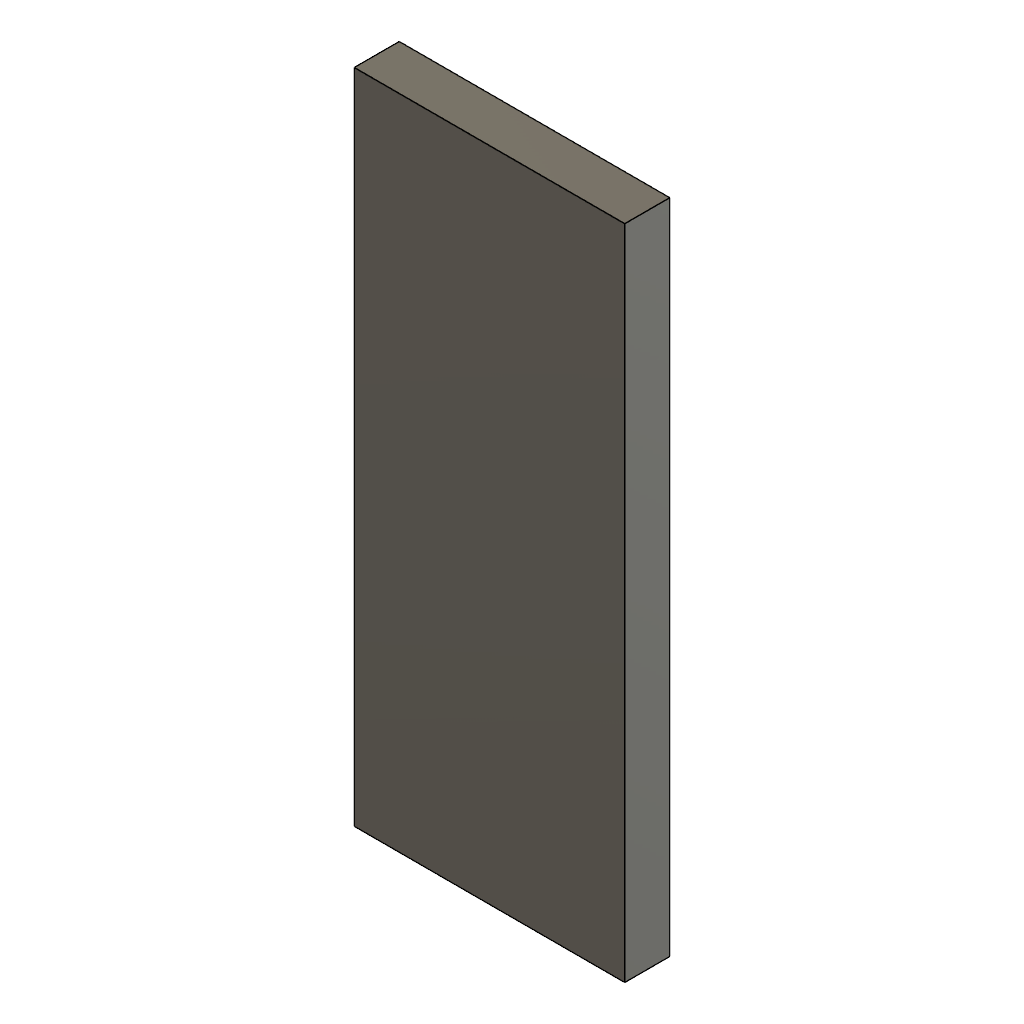
Switchn't (Autodesk Fusion 360 archive; units mm, degrees)
design "Pico"
part number: 2026-10-30-01-21-40-497
Autodesk Fusion 360 part; units mm, degrees
sketch "Sketch1" plane through (0, 0, 0) normal (0, 0, 1) x (1, 0, 0)
  line L0 (-10.5, -25.5) -> (10.5, -25.5)
  line L1 (10.5, -25.5) -> (10.5, 25.5)
  line L2 (10.5, 25.5) -> (-10.5, 25.5)
  line L3 (-10.5, 25.5) -> (-10.5, -25.5)
  line L4 (-10.5, -25.5) -> (10.5, 25.5) construction
  line L5 (10.5, -25.5) -> (-10.5, 25.5) construction
  dimension "d1" = 21
  dimension "d2" = 51
  constraint horizontal L0
  constraint perpendicular L0 L1
  constraint parallel L0 L2
  constraint parallel L1 L3
  constraint coincident L4 origin
  constraint coincident L5 origin
  measures "d1" distance of L1.end L2.end
  measures "d2" distance of L0.end L1.end
extrude "Extrude1" add sketch "Sketch1" along normal blind 3.5

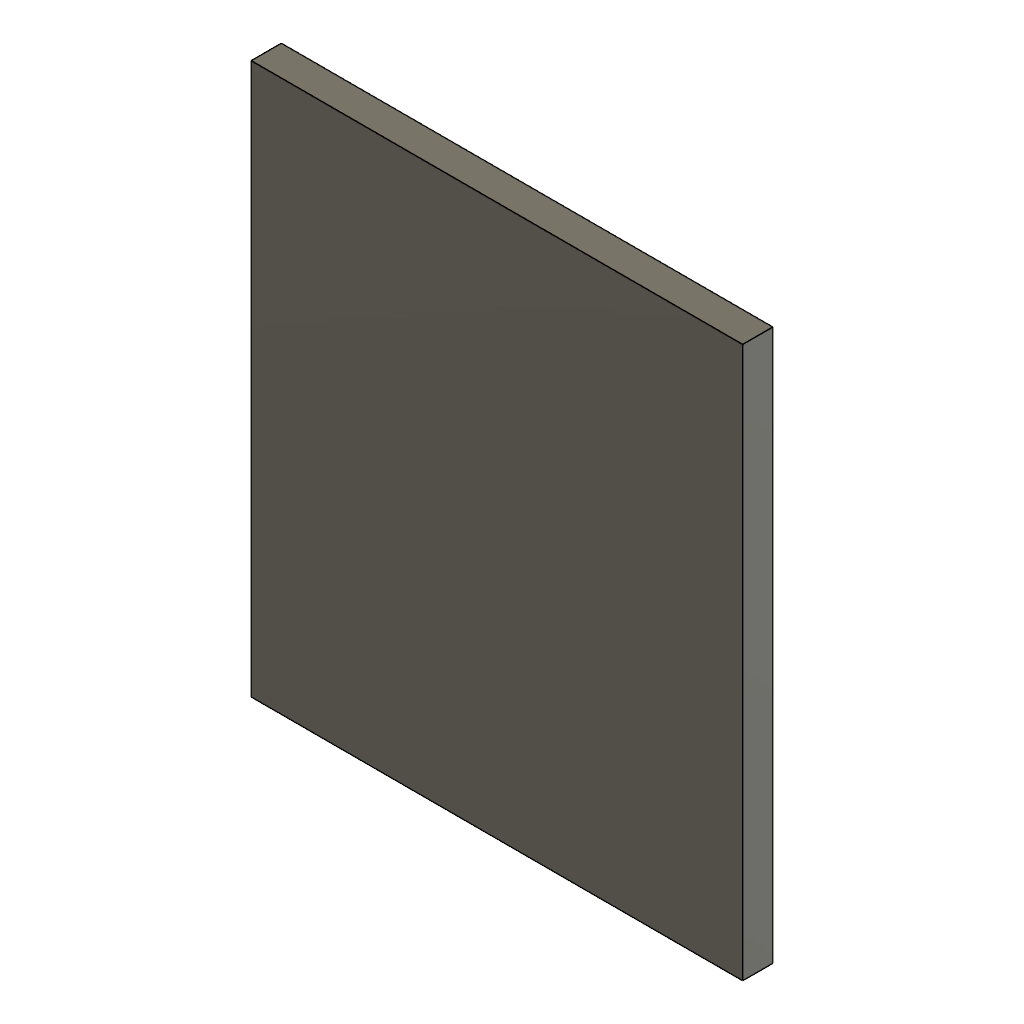
design "display"
part number: 2026-10-30-01-13-21-698
Autodesk Fusion 360 part; units mm, degrees
sketch "Sketch1" plane through (0, 0, 0) normal (0, 0, 1) x (1, 0, 0)
  line L0 (13, 14.575) -> (-13, 14.575)
  line L1 (-13, 14.575) -> (-13, -14.575)
  line L2 (-13, -14.575) -> (13, -14.575)
  line L3 (13, -14.575) -> (13, 14.575)
  line L4 (13, 14.575) -> (-13, -14.575) construction
  line L5 (-13, 14.575) -> (13, -14.575) construction
  dimension "d1" = 26
  dimension "d2" = 29.15
  constraint horizontal L0
  constraint perpendicular L0 L1
  constraint parallel L0 L2
  constraint parallel L1 L3
  constraint coincident L4 origin
  constraint coincident L5 origin
  measures "d1" distance of L1.end L2.end
  measures "d2" distance of L0.end L1.end
extrude "Extrude1" add sketch "Sketch1" along normal blind 1.6

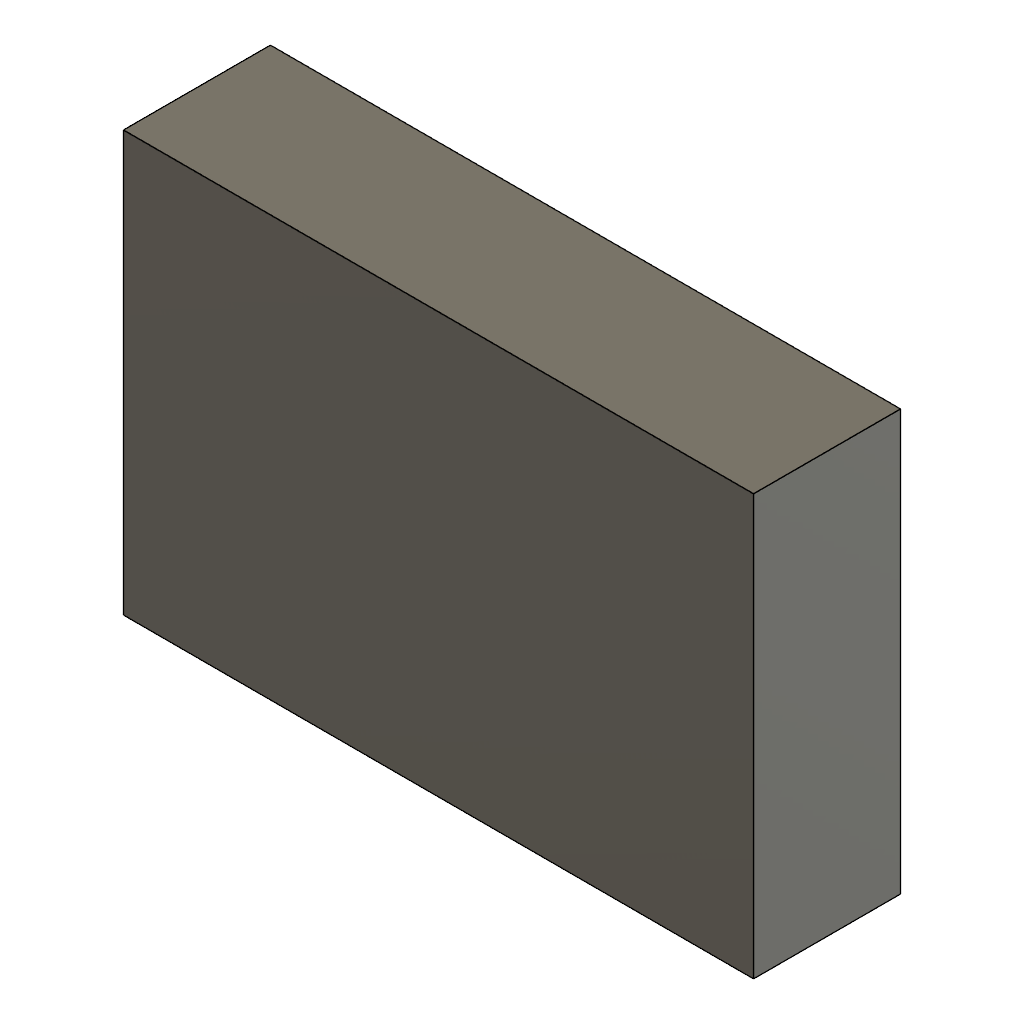
design "Speaker"
part number: 2026-10-30-01-26-45-037
Autodesk Fusion 360 part; units mm, degrees
sketch "Sketch1" plane through (0, 0, 0) normal (0, 0, 1) x (1, 0, 0)
  line L0 (-15, -10) -> (15, -10)
  line L1 (15, -10) -> (15, 10)
  line L2 (15, 10) -> (-15, 10)
  line L3 (-15, 10) -> (-15, -10)
  line L4 (-15, -10) -> (15, 10) construction
  line L5 (15, -10) -> (-15, 10) construction
  dimension "d1" = 30
  dimension "d2" = 20
  constraint horizontal L0
  constraint perpendicular L0 L1
  constraint parallel L0 L2
  constraint parallel L1 L3
  constraint coincident L4 origin
  constraint coincident L5 origin
  measures "d1" distance of L1.end L2.end
  measures "d2" distance of L0.end L1.end
extrude "Extrude1" add sketch "Sketch1" along normal blind 7

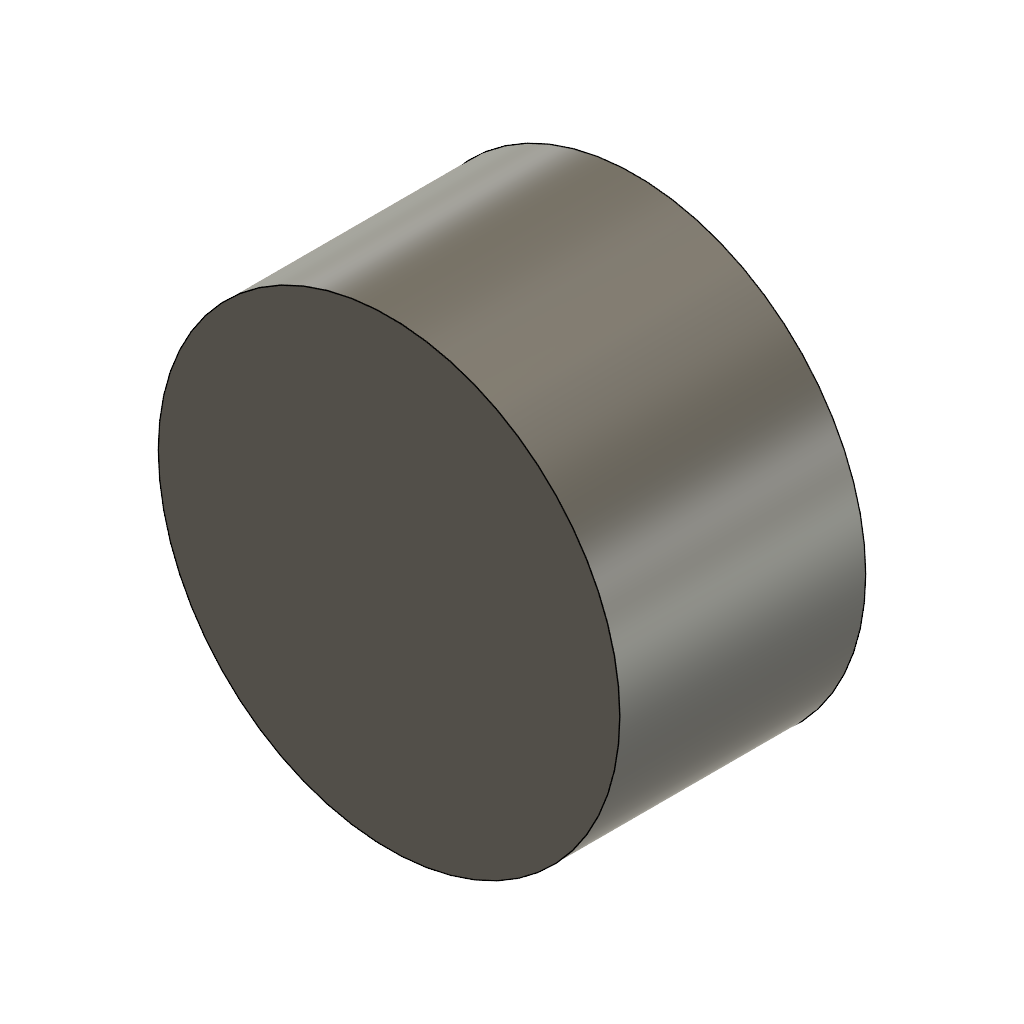
design "Buzzer"
part number: 2026-10-30-01-23-30-754
Autodesk Fusion 360 part; units mm, degrees
sketch "Sketch1" plane through (0, 0, 0) normal (0, 0, 1) x (1, 0, 0)
  circle A0 centre (0, 0) radius 6.1
  dimension "d1" = 12.2
  constraint coincident A0.centre origin
  measures "d1" diameter of A0
extrude "Extrude1" add sketch "Sketch1" along normal blind 6.5

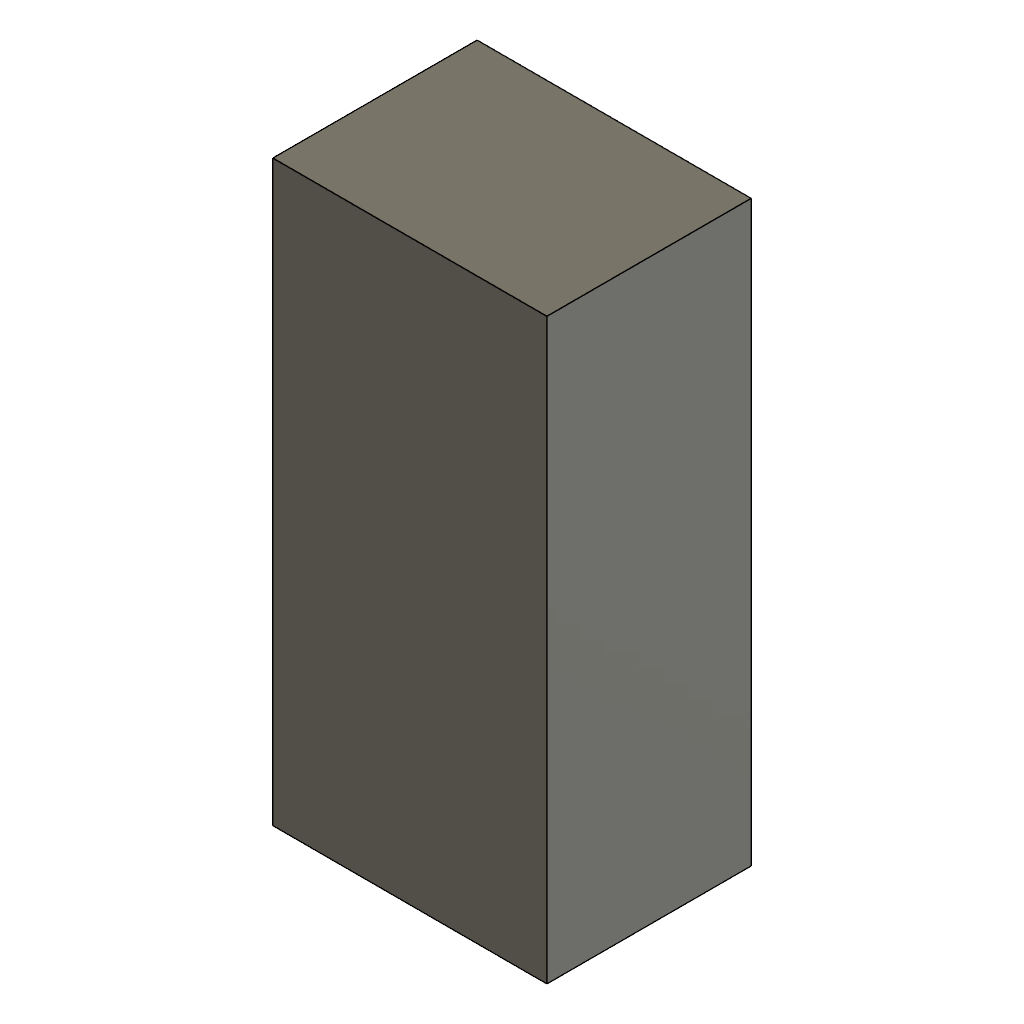
design "Slidey switch"
part number: 2026-10-30-01-30-20-062
Autodesk Fusion 360 part; units mm, degrees
sketch "Sketch1" plane through (0, 0, 0) normal (0, 0, 1) x (1, 0, 0)
  line L0 (-0.3946, -5.8) -> (5.1054, -5.8)
  line L1 (5.1054, -5.8) -> (5.1054, 5.8)
  line L2 (5.1054, 5.8) -> (-0.3946, 5.8)
  line L3 (-0.3946, 5.8) -> (-0.3946, -5.8)
  line L4 (-0.3946, -5.8) -> (5.1054, 5.8) construction
  line L5 (5.1054, -5.8) -> (-0.3946, 5.8) construction
  point P0 (2.3554, 0)
  dimension "d1" = 5.5
  dimension "d2" = 11.6
  constraint horizontal L0
  constraint perpendicular L0 L1
  constraint parallel L0 L2
  constraint parallel L1 L3
  constraint coincident L4 P0
  constraint coincident L5 P0
  measures "d1" distance of L1.end L2.end
  measures "d2" distance of L0.end L1.end
extrude "Extrude1" add sketch "Sketch1" along normal blind 4.1

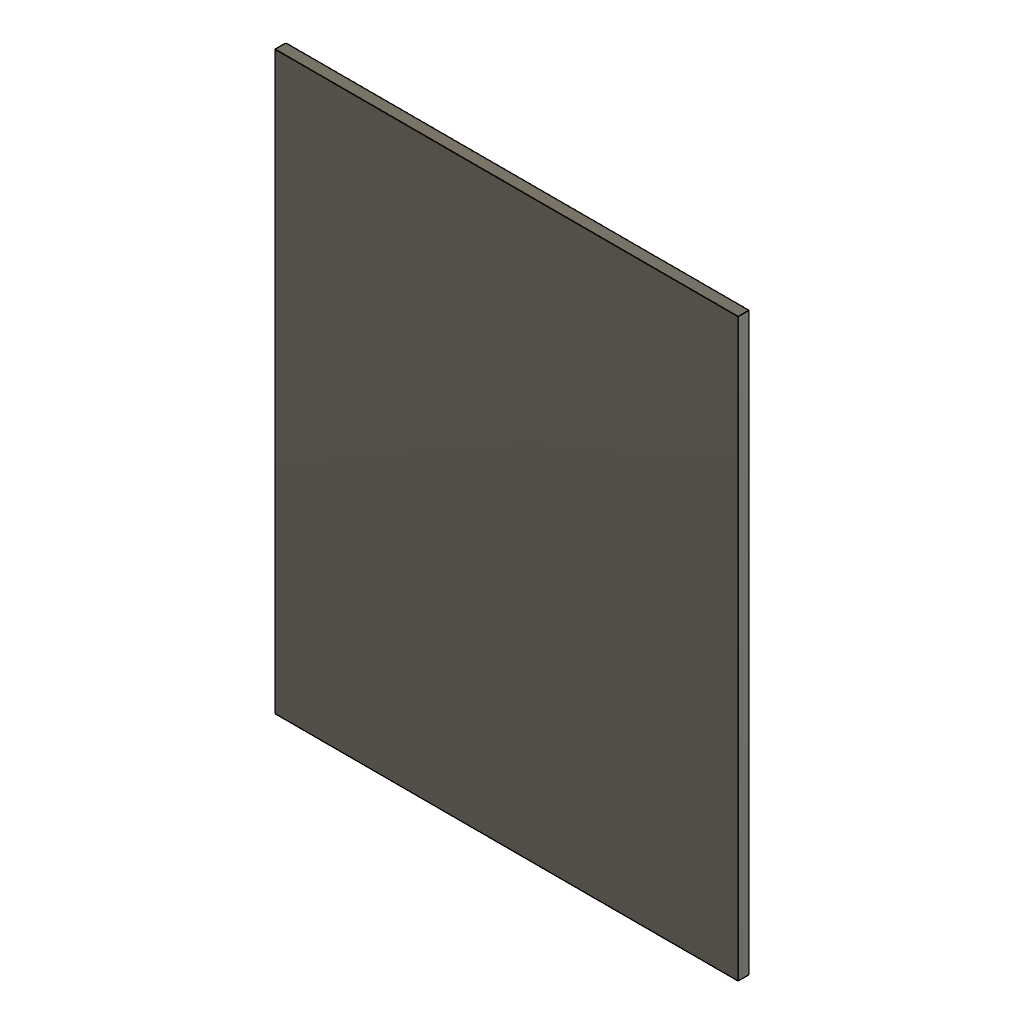
design "PCB"
part number: 2026-10-30-01-00-50-641
Autodesk Fusion 360 part; units mm, degrees
sketch "Sketch1" plane through (0, 0, 0) normal (0, 0, 1) x (1, 0, 0)
  line L0 (34, 42.25) -> (-34, 42.25)
  line L1 (-34, 42.25) -> (-34, -42.25)
  line L2 (-34, -42.25) -> (34, -42.25)
  line L3 (34, -42.25) -> (34, 42.25)
  line L4 (34, 42.25) -> (-34, -42.25) construction
  line L5 (-34, 42.25) -> (34, -42.25) construction
  dimension "d10" = 68
  dimension "d11" = 84.5
  constraint horizontal L0
  constraint perpendicular L0 L1
  constraint parallel L0 L2
  constraint parallel L1 L3
  constraint coincident L4 origin
  constraint coincident L5 origin
  measures "d10" distance of L1.end L2.end
  measures "d11" distance of L0.end L1.end
extrude "Extrude1" add sketch "Sketch1" along normal blind 1.6
equation "PCBwidth = 68 mm"
equation "PCBlength = 84.5 mm"
equation "PCBheight = 1.6 mm"
equation "Clearence = 0.3 mm"
equation "Wallthickness = 2 mm"
equation "insidewidth = 70 mm"
equation "outsidewidth = insidewidth + ( 2 * Wallthickness )"
equation "insidelength = PCBlength + ( 2 * Clearence )"
equation "outsidelength = insidelength + ( 2 * Wallthickness )"
equation "d10 = PCBwidth"
equation "d11 = PCBlength"

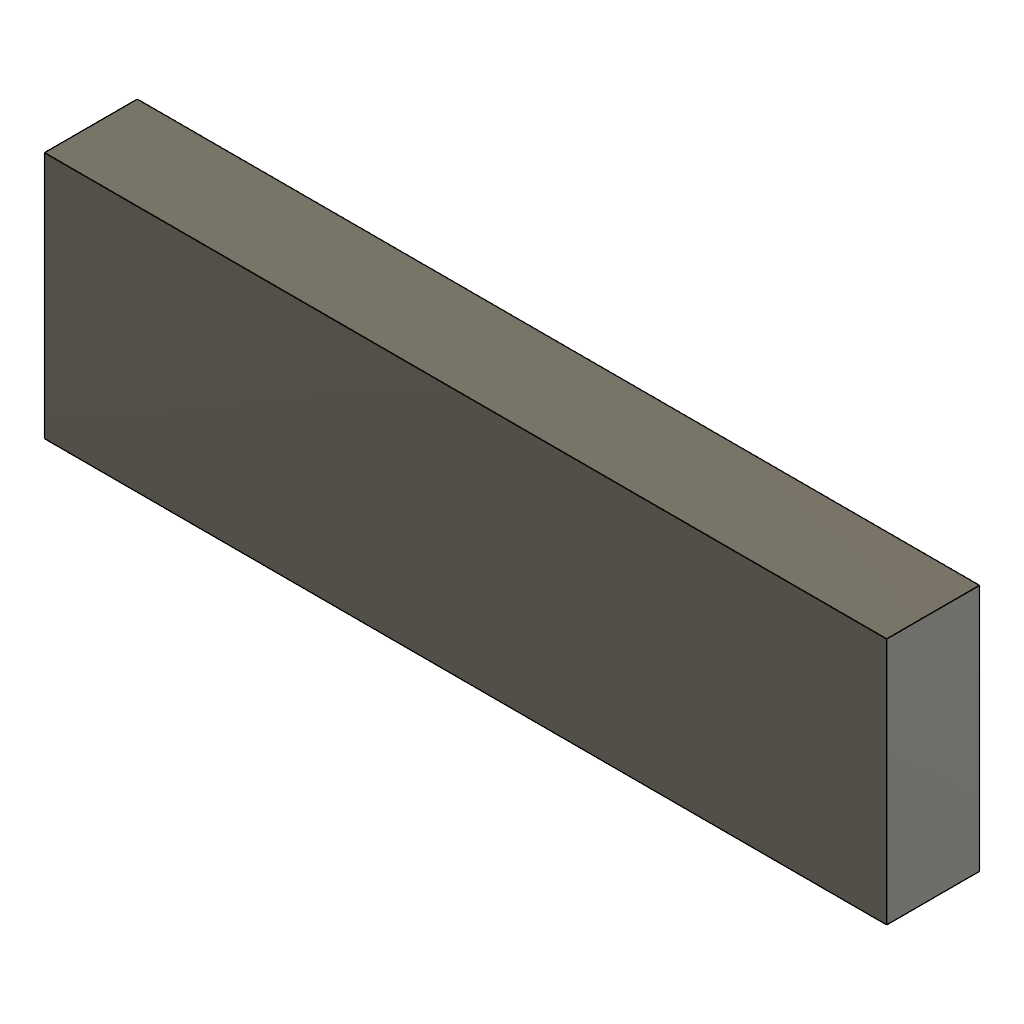
design "battery"
part number: 2026-10-30-00-52-14-588
Autodesk Fusion 360 part; units mm, degrees
sketch "Sketch1" plane through (0, 0, 0) normal (0, 0, 1) x (1, 0, 0)
  line L0 (34, 10) -> (-34, 10)
  line L1 (-34, 10) -> (-34, -10)
  line L2 (-34, -10) -> (34, -10)
  line L3 (34, -10) -> (34, 10)
  line L4 (34, 10) -> (-34, -10) construction
  line L5 (-34, 10) -> (34, -10) construction
  dimension "d1" = 68
  dimension "d2" = 20
  constraint horizontal L0
  constraint perpendicular L0 L1
  constraint parallel L0 L2
  constraint parallel L1 L3
  constraint coincident L4 origin
  constraint coincident L5 origin
  measures "d1" distance of L1.end L2.end
  measures "d2" distance of L0.end L1.end
extrude "Extrude1" add sketch "Sketch1" along normal blind 7.5
move_body "Move1" bodies 1 to x (1, 0, 0) y (0, 1, 0) z (0, 0, 1) at (0, -23, 0)

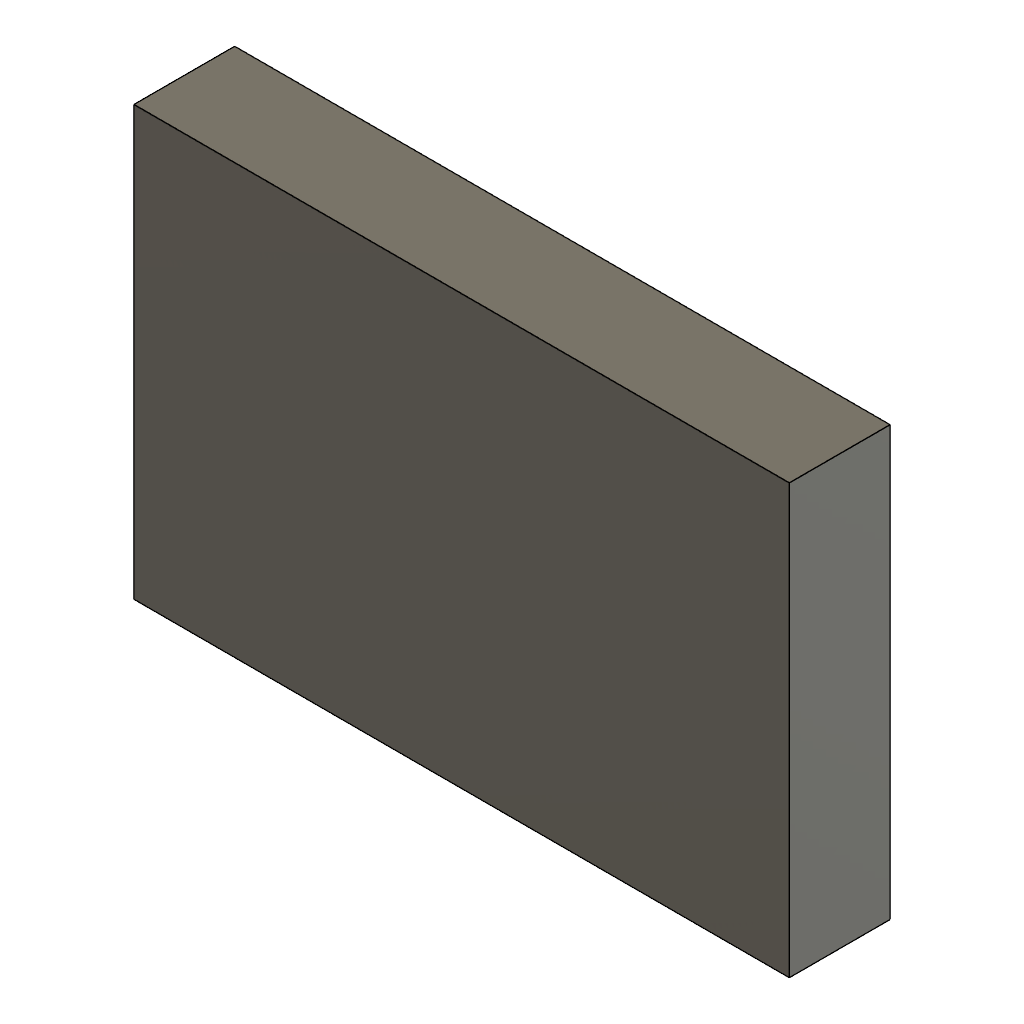
design "Charger"
part number: 2026-10-30-01-28-38-933
Autodesk Fusion 360 part; units mm, degrees
sketch "Sketch1" plane through (0, 0, 0) normal (0, 0, 1) x (1, 0, 0)
  line L0 (-13, -8.5) -> (13, -8.5)
  line L1 (13, -8.5) -> (13, 8.5)
  line L2 (13, 8.5) -> (-13, 8.5)
  line L3 (-13, 8.5) -> (-13, -8.5)
  line L4 (-13, -8.5) -> (13, 8.5) construction
  line L5 (13, -8.5) -> (-13, 8.5) construction
  dimension "d1" = 26
  dimension "d2" = 17
  constraint horizontal L0
  constraint perpendicular L0 L1
  constraint parallel L0 L2
  constraint parallel L1 L3
  constraint coincident L4 origin
  constraint coincident L5 origin
  measures "d1" distance of L1.end L2.end
  measures "d2" distance of L0.end L1.end
extrude "Extrude1" add sketch "Sketch1" along normal blind 4

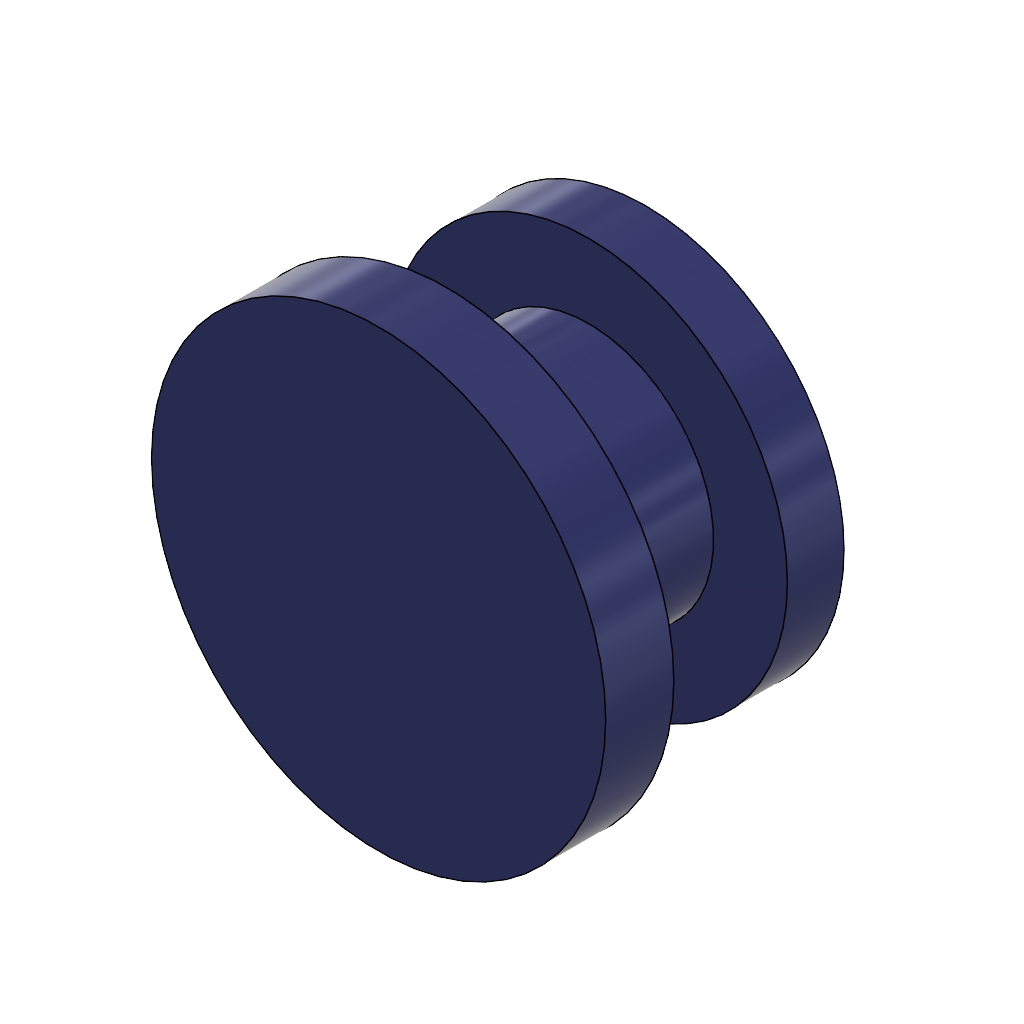
design "keycaps"
part number: 2026-10-30-20-06-01-005
Autodesk Fusion 360 part; units mm, degrees
sketch "Sketch1" plane through (0, 0, 0) normal (0, 0, 1) x (1, 0, 0)
  circle A0 centre (0, 0) radius 3.5
  dimension "d1" = 7
  constraint coincident A0.centre origin
  measures "d1" diameter of A0
extrude "Extrude1" add sketch "Sketch1" against normal blind 1
sketch "Sketch2" plane through (0, 0, 0) normal (0, 0, 1) x (1, 0, 0)
  circle A0 centre (0, 0) radius 2.2
  dimension "d4" = 4.4
  constraint coincident A0.centre origin
  measures "d4" diameter of A0
extrude "Extrude2" add sketch "Sketch2" along normal blind 2.5
sketch "Sketch3" plane through (0, 0, 0) normal (0, 0, 1) x (1, 0, 0)
  circle A0 through (4, 0, 2.5) (-2, 3.4641, 2.5) (-2, -3.4641, 2.5)
  circle A1 through (2.2, 0, 2.5) (-1.1, 1.9053, 2.5) (-1.1, -1.9053, 2.5)
  dimension "d7" = 8
extrude "Extrude3" add sketch "Sketch3" along normal blind 1.2 contours A0 | A1 in plane through (0, 0, 2.5) normal (0, 0, 1)

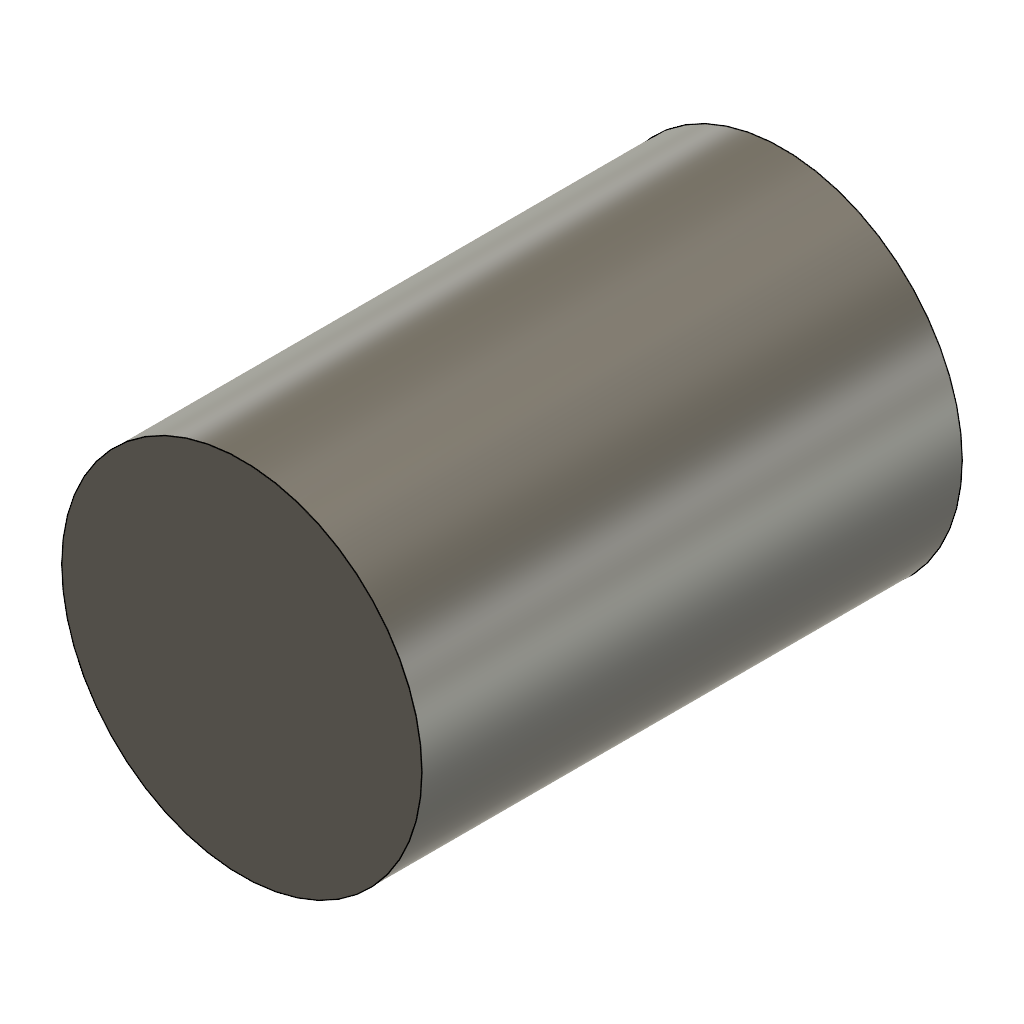
design "Capacitor"
part number: 2026-10-30-01-25-13-755
Autodesk Fusion 360 part; units mm, degrees
sketch "Sketch1" plane through (0, 0, 0) normal (0, 0, 1) x (1, 0, 0)
  circle A0 centre (0, 0) radius 4
  dimension "d1" = 8
  constraint coincident A0.centre origin
  measures "d1" diameter of A0
extrude "Extrude1" add sketch "Sketch1" along normal blind 12

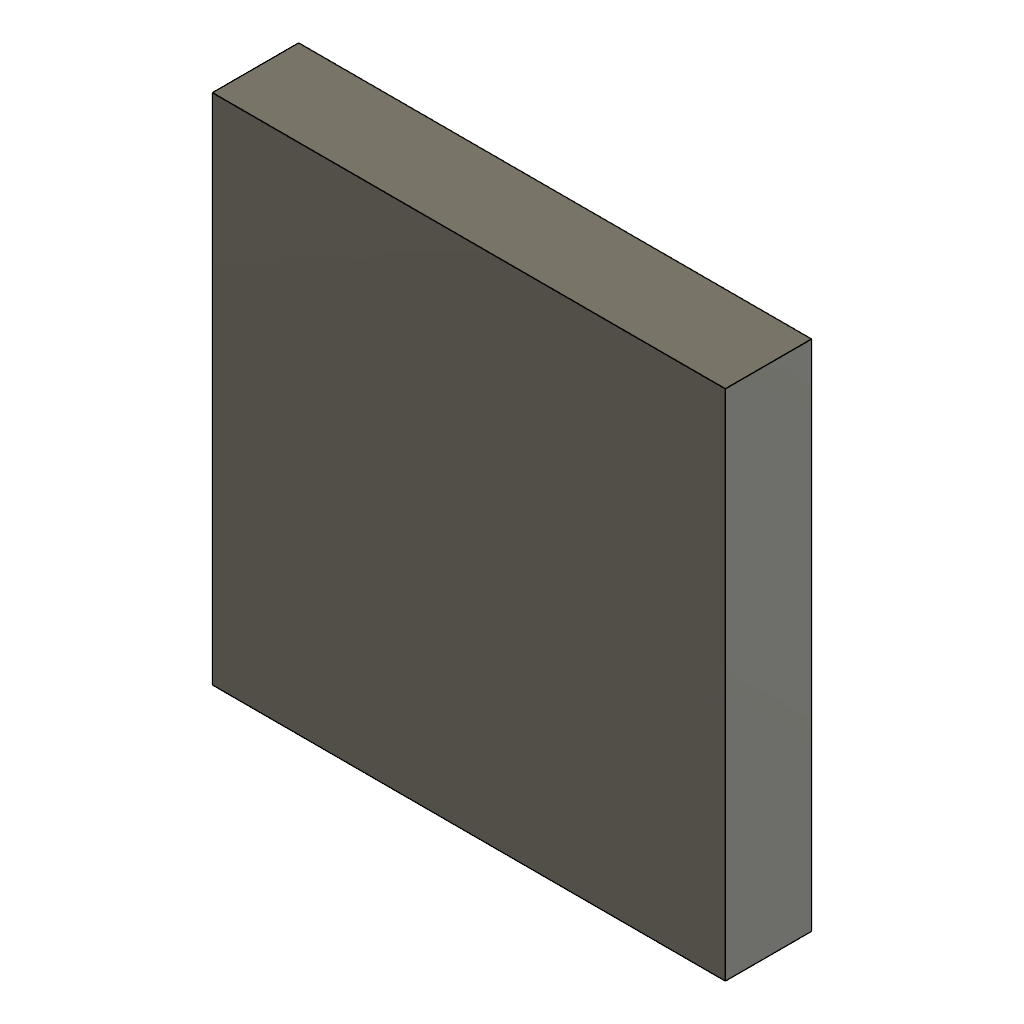
design "MP3 module"
part number: 2026-10-30-01-17-09-769
Autodesk Fusion 360 part; units mm, degrees
sketch "Sketch1" plane through (0, 0, 0) normal (0, 0, 1) x (1, 0, 0)
  line L0 (10.4, 10.4) -> (-10.4, 10.4)
  line L1 (-10.4, 10.4) -> (-10.4, -10.4)
  line L2 (-10.4, -10.4) -> (10.4, -10.4)
  line L3 (10.4, -10.4) -> (10.4, 10.4)
  line L4 (10.4, 10.4) -> (-10.4, -10.4) construction
  line L5 (-10.4, 10.4) -> (10.4, -10.4) construction
  dimension "d1" = 20.8
  dimension "d2" = 20.8
  constraint horizontal L0
  constraint perpendicular L0 L1
  constraint parallel L0 L2
  constraint parallel L1 L3
  constraint coincident L4 origin
  constraint coincident L5 origin
  measures "d1" distance of L1.end L2.end
  measures "d2" distance of L0.end L1.end
extrude "Extrude1" add sketch "Sketch1" along normal blind 3.5
